DRR_D1_net (Autodesk Fusion 360 design; units mm, degrees)
part number: 2026-11-05-15-11-59-362
part number: 2026-11-05-15-12-06-884
part number: 2026-11-05-15-12-08-427
Autodesk Fusion 360 part; units mm, degrees
sketch "Sketch1" plane through (0, 0, 0) normal (0, 0, 1) x (1, 0, 0) in component "Net Posts"
  line L0 (-200, 3310) -> (200, 3310)
  line L1 (200, 3310) -> (200, 3710)
  line L2 (200, 3710) -> (-200, 3710)
  line L3 (-200, 3710) -> (-200, 3310)
  dimension "d90" = 200
  dimension "d91" = 3310
  dimension "d92" = 200
  dimension "d93" = 3710
  constraint horizontal L0.start L0.end
  constraint vertical L0.end L1.end
  constraint vertical L0.start L2.end
  constraint horizontal L1.end L2.end
  measures "d90" horizontal distance of origin L0.start
  measures "d91" vertical distance of origin L0.start
  measures "d92" horizontal distance of origin L0.end
  measures "d93" vertical distance of origin L1.end
extrude "Extrude1" add sketch "Sketch1" along normal blind 8 makes body 1 in component "Net Posts"
sketch "Sketch2" plane through (0, 0, 0) normal (0, 0, 1) x (1, 0, 0) in component "Net Posts"
  line L0 (-60, 3450) -> (60, 3450)
  line L1 (60, 3450) -> (60, 3570)
  line L2 (60, 3570) -> (-60, 3570)
  line L3 (-60, 3570) -> (-60, 3450)
  dimension "d96" = 60
  dimension "d97" = 3450
  dimension "d98" = 60
  dimension "d99" = 3570
  constraint horizontal L0.start L0.end
  constraint vertical L0.end L1.end
  constraint vertical L0.start L2.end
  constraint horizontal L1.end L2.end
  measures "d96" horizontal distance of origin L0.start
  measures "d97" vertical distance of origin L0.start
  measures "d98" horizontal distance of origin L0.end
  measures "d99" vertical distance of origin L1.end
extrude "Extrude2" add sketch "Sketch2" along normal blind 1992 from surface at 8 separate body makes body 2 in component "Net Posts"
sketch "Sketch3" plane through (0, 0, 0) normal (0, 1, 0) x (1, 0, 0) in component "Net Posts"
  line L0 (60, -1700) -> (60, -1580)
  line L1 (60, -1580) -> (1380, -8)
  line L2 (1380, -8) -> (1500, -8)
  line L3 (1500, -8) -> (60, -1700)
  dimension "d103" = 60
  dimension "d104" = 1700
  dimension "d105" = 1580
  dimension "d106" = 1380
  constraint vertical L0.start L0.end
  constraint horizontal L1.end L2.end
  measures "d103" horizontal distance of origin L0.start
  measures "d104" vertical distance of origin L0.start
  measures "d105" vertical distance of origin L0.end
  measures "d106" horizontal distance of origin L1.end
extrude "Extrude3" add sketch "Sketch3" along normal blind 80 from surface at 3470 separate body makes body 3 in component "Net Posts"
sketch "Sketch4" plane through (0, 0, 0) normal (0, 0, 1) x (1, 0, 0) in component "Net Posts"
  line L0 (1250, 3360) -> (1550, 3360)
  line L1 (1550, 3360) -> (1550, 3660)
  line L2 (1550, 3660) -> (1250, 3660)
  line L3 (1250, 3660) -> (1250, 3360)
  dimension "d112" = 1250
  dimension "d113" = 3360
  dimension "d114" = 1550
  dimension "d115" = 3660
  constraint horizontal L0.start L0.end
  constraint vertical L0.end L1.end
  constraint vertical L0.start L2.end
  constraint horizontal L1.end L2.end
  measures "d112" horizontal distance of origin L0.start
  measures "d113" vertical distance of origin L0.start
  measures "d114" horizontal distance of origin L0.end
  measures "d115" vertical distance of origin L1.end
extrude "Extrude4" add sketch "Sketch4" along normal blind 8 separate body makes body 4 in component "Net Posts"
sketch "Sketch5" plane through (0, 0, 0) normal (0, 0, 1) x (1, 0, 0) in component "Net Posts"
  line L0 (-200, -3710) -> (200, -3710)
  line L1 (200, -3710) -> (200, -3310)
  line L2 (200, -3310) -> (-200, -3310)
  line L3 (-200, -3310) -> (-200, -3710)
  dimension "d118" = 200
  dimension "d119" = 3710
  dimension "d120" = 200
  dimension "d121" = 3310
  constraint horizontal L0.start L0.end
  constraint vertical L0.end L1.end
  constraint vertical L0.start L2.end
  constraint horizontal L1.end L2.end
  measures "d118" horizontal distance of origin L0.start
  measures "d119" vertical distance of origin L0.start
  measures "d120" horizontal distance of origin L0.end
  measures "d121" vertical distance of origin L1.end
extrude "Extrude5" add sketch "Sketch5" along normal blind 8 separate body makes body 5 in component "Net Posts"
sketch "Sketch6" plane through (0, 0, 0) normal (0, 0, 1) x (1, 0, 0) in component "Net Posts"
  line L0 (-60, -3570) -> (60, -3570)
  line L1 (60, -3570) -> (60, -3450)
  line L2 (60, -3450) -> (-60, -3450)
  line L3 (-60, -3450) -> (-60, -3570)
  dimension "d124" = 60
  dimension "d125" = 3570
  dimension "d126" = 60
  dimension "d127" = 3450
  constraint horizontal L0.start L0.end
  constraint vertical L0.end L1.end
  constraint vertical L0.start L2.end
  constraint horizontal L1.end L2.end
  measures "d124" horizontal distance of origin L0.start
  measures "d125" vertical distance of origin L0.start
  measures "d126" horizontal distance of origin L0.end
  measures "d127" vertical distance of origin L1.end
extrude "Extrude6" add sketch "Sketch6" along normal blind 1992 from surface at 8 separate body makes body 6 in component "Net Posts"
sketch "Sketch7" plane through (0, 0, 0) normal (0, 1, 0) x (1, 0, 0) in component "Net Posts"
  line L0 (60, -1700) -> (60, -1580)
  line L1 (60, -1580) -> (1380, -8)
  line L2 (1380, -8) -> (1500, -8)
  line L3 (1500, -8) -> (60, -1700)
  dimension "d131" = 60
  dimension "d132" = 1700
  dimension "d133" = 1580
  dimension "d134" = 1380
  constraint vertical L0.start L0.end
  constraint horizontal L1.end L2.end
  measures "d131" horizontal distance of origin L0.start
  measures "d132" vertical distance of origin L0.start
  measures "d133" vertical distance of origin L0.end
  measures "d134" horizontal distance of origin L1.end
extrude "Extrude7" add sketch "Sketch7" along normal blind 80 from surface at -3550 separate body makes body 7 in component "Net Posts"
sketch "Sketch8" plane through (0, 0, 0) normal (0, 0, 1) x (1, 0, 0) in component "Net Posts"
  line L0 (1250, -3660) -> (1550, -3660)
  line L1 (1550, -3660) -> (1550, -3360)
  line L2 (1550, -3360) -> (1250, -3360)
  line L3 (1250, -3360) -> (1250, -3660)
  dimension "d140" = 1250
  dimension "d141" = 3660
  dimension "d142" = 1550
  dimension "d143" = 3360
  constraint horizontal L0.start L0.end
  constraint vertical L0.end L1.end
  constraint vertical L0.start L2.end
  constraint horizontal L1.end L2.end
  measures "d140" horizontal distance of origin L0.start
  measures "d141" vertical distance of origin L0.start
  measures "d142" horizontal distance of origin L0.end
  measures "d143" vertical distance of origin L1.end
extrude "Extrude8" add sketch "Sketch8" along normal blind 8 separate body makes body 8 in component "Net Posts"
sketch "Sketch1 (2)" plane through (0, 0, 0) normal (0, 0, 1) x (1, 0, 0) in component "Net Mesh"
  line L0 (-6, -3450) -> (6, -3450)
  line L1 (6, -3450) -> (6, -3438)
  line L2 (6, -3438) -> (-6, -3438)
  line L3 (-6, -3438) -> (-6, -3450)
  dimension "d146" = 6
  dimension "d147" = 3450
  dimension "d148" = 6
  dimension "d149" = 3438
  constraint horizontal L0.start L0.end
  constraint vertical L0.end L1.end
  constraint vertical L0.start L2.end
  constraint horizontal L1.end L2.end
  measures "d146" horizontal distance of origin L0.start
  measures "d147" vertical distance of origin L0.start
  measures "d148" horizontal distance of origin L0.end
  measures "d149" vertical distance of origin L1.end
extrude "Extrude1'" add sketch "Sketch1 (2)" along normal blind 1650 from surface at 150 separate body makes body 9 in component "Net Mesh"
pattern_linear "R-Pattern1" count 29 spacing 246 along (0, 1, 0) count 3 spacing 0 along (0, 1, 0) of bodies 9 makes body 10 at (-6, -3196, 1250) makes body 11 at (-6, -2950, 1250) makes body 12 at (-6, -2704, 1250) makes body 13 at (-6, -2458, 1250) makes body 14 at (-6, -2212, 1250) makes body 15 at (-6, -1966, 1250) makes body 16 at (-6, -1720, 1250) makes body 17 at (-6, -1474, 1250) makes body 18 at (-6, -1228, 1250) makes body 19 at (-6, -982, 1250) makes body 20 at (-6, -736, 1250) makes body 21 at (-6, -490, 1250) makes body 22 at (-6, -244, 1250) makes body 23 at (-6, 2, 1250) makes body 24 at (-6, 248, 1250) makes body 25 at (-6, 494, 1250) makes body 26 at (-6, 740, 1250) makes body 27 at (-6, 986, 1250) makes body 28 at (-6, 1232, 1250) makes body 29 at (-6, 1478, 1250) makes body 30 at (-6, 1724, 1250) makes body 31 at (-6, 1970, 1250) makes body 32 at (-6, 2216, 1250) makes body 33 at (-6, 2462, 1250) makes body 34 at (-6, 2708, 1250) makes body 35 at (-6, 2954, 1250) makes body 36 at (-6, 3200, 1250) makes body 37 at (-6, 3446, 1250) makes body 38 at (-6, -3442, 1250) makes body 39 at (-6, -3196, 1250) makes body 40 at (-6, -2950, 1250) makes body 41 at (-6, -2704, 1250) makes body 42 at (-6, -2458, 1250) makes body 43 at (-6, -2212, 1250) makes body 44 at (-6, -1966, 1250) makes body 45 at (-6, -1720, 1250) makes body 46 at (-6, -1474, 1250) makes body 47 at (-6, -1228, 1250) makes body 48 at (-6, -982, 1250) makes body 49 at (-6, -736, 1250) makes body 50 at (-6, -490, 1250) makes body 51 at (-6, -244, 1250) makes body 52 at (-6, 2, 1250) makes body 53 at (-6, 248, 1250) makes body 54 at (-6, 494, 1250) makes body 55 at (-6, 740, 1250) makes body 56 at (-6, 986, 1250) makes body 57 at (-6, 1232, 1250) makes body 58 at (-6, 1478, 1250) makes body 59 at (-6, 1724, 1250) makes body 60 at (-6, 1970, 1250) makes body 61 at (-6, 2216, 1250) makes body 62 at (-6, 2462, 1250) makes body 63 at (-6, 2708, 1250) makes body 64 at (-6, 2954, 1250) makes body 65 at (-6, 3200, 1250) makes body 66 at (-6, 3446, 1250) makes body 67 at (-6, -3442, 1250) makes body 68 at (-6, -3196, 1250) makes body 69 at (-6, -2950, 1250) makes body 70 at (-6, -2704, 1250) makes body 71 at (-6, -2458, 1250) makes body 72 at (-6, -2212, 1250) makes body 73 at (-6, -1966, 1250) makes body 74 at (-6, -1720, 1250) makes body 75 at (-6, -1474, 1250) makes body 76 at (-6, -1228, 1250) makes body 77 at (-6, -982, 1250) makes body 78 at (-6, -736, 1250) makes body 79 at (-6, -490, 1250) makes body 80 at (-6, -244, 1250) makes body 81 at (-6, 2, 1250) makes body 82 at (-6, 248, 1250) makes body 83 at (-6, 494, 1250) makes body 84 at (-6, 740, 1250) makes body 85 at (-6, 986, 1250) makes body 86 at (-6, 1232, 1250) makes body 87 at (-6, 1478, 1250) makes body 88 at (-6, 1724, 1250) makes body 89 at (-6, 1970, 1250) makes body 90 at (-6, 2216, 1250) makes body 91 at (-6, 2462, 1250) makes body 92 at (-6, 2708, 1250) makes body 93 at (-6, 2954, 1250) makes body 94 at (-6, 3200, 1250) makes body 95 at (-6, 3446, 1250) in component "Net Mesh"
sketch "Sketch2 (2)" plane through (0, 0, 0) normal (0, 1, 0) x (1, 0, 0) in component "Net Mesh"
  line L0 (-6, -150) -> (6, -150)
  line L1 (6, -150) -> (6, -162)
  line L2 (6, -162) -> (-6, -162)
  line L3 (-6, -162) -> (-6, -150)
  dimension "d157" = 6
  dimension "d159" = 6
  constraint horizontal L0.start L0.end
  constraint vertical L0.end L1.end
  constraint vertical L0.start L2.end
  constraint horizontal L1.end L2.end
  measures "d157" horizontal distance of origin L0.start
  measures "d159" horizontal distance of origin L0.end
extrude "Extrude2'" add sketch "Sketch2 (2)" along normal blind 6900 from surface at -3450 separate body makes body 96 in component "Net Mesh"
pattern_linear "R-Pattern2" count 8 spacing 234 along (0, 0, 1) count 3 spacing 0 along (0, 0, 1) of bodies 96 makes body 97 at (-2, 1150, 384) makes body 98 at (-2, 1150, 618) makes body 99 at (-2, 1150, 852) makes body 100 at (-2, 1150, 1086) makes body 101 at (-2, 1150, 1320) makes body 102 at (-2, 1150, 1554) makes body 103 at (-2, 1150, 1788) makes body 104 at (-2, 1150, 150) makes body 105 at (-2, 1150, 384) makes body 106 at (-2, 1150, 618) makes body 107 at (-2, 1150, 852) makes body 108 at (-2, 1150, 1086) makes body 109 at (-2, 1150, 1320) makes body 110 at (-2, 1150, 1554) makes body 111 at (-2, 1150, 1788) makes body 112 at (-2, 1150, 150) makes body 113 at (-2, 1150, 384) makes body 114 at (-2, 1150, 618) makes body 115 at (-2, 1150, 852) makes body 116 at (-2, 1150, 1086) makes body 117 at (-2, 1150, 1320) makes body 118 at (-2, 1150, 1554) makes body 119 at (-2, 1150, 1788) in component "Net Mesh"
component "Net Posts" placed x (1, 0, 0) y (0, 1, 0) z (0, 0, 1) at (0, 0, 0)
component "Net Mesh" placed x (1, 0, 0) y (0, 1, 0) z (0, 0, 1) at (0, 0, 0)
equation "drone_mass = 140.6 kg" comment "spec: drone mass (310 lb)"
equation "wingspan = 6100 mm" comment "spec: stand-in wingspan (20 ft)"
equation "body_width = 508 mm" comment "spec: body width, design value"
equation "body_drop = 254 mm" comment "spec: wing underside to body bottom"
equation "prop_dia = 700 mm" comment "spec: prop diameter, stopped blades vertical"
equation "tail_clear = 330 mm" comment "spec: tail underside above wing underside (drone requirement, 5 deg landing pitch)"
equation "landing_speed_kn = 40" comment "spec: landing speed, knots"
equation "sink_rate_ms = 1.5" comment "spec: sink rate at touchdown, m/s"
equation "grip = 0.3" comment "spec: friction coefficient, cap on wing"
equation "max_offset = 300 mm" comment "spec: side-to-side landing error"
equation "side_clear = 25 mm" comment "spec: gap between body and cap each side"
equation "rail_gap = body_width + 2 * side_clear" comment "spec: inner gap between caps"
equation "cap_width = 150 mm" comment "spec"
equation "cap_wall = 2 mm" comment "spec (was 3 mm; 2 mm for the 25 kg target)"
equation "cap_overlap = 100 mm" comment "spec: shingle overlap at joints"
equation "core_w = 50 mm" comment "spec: aluminium core tube width"
equation "core_h = 100 mm" comment "spec: aluminium core tube height"
equation "core_wall = 2 mm" comment "spec (was 3 mm; 2 mm for the 25 kg target)"
equation "rail_top_h = 700 mm" comment "spec: ground to cap top, unloaded"
equation "section_len = 2000 mm" comment "spec (was 2400 mm; 2000 mm for the 25 kg target)"
equation "frame_inset = 300 mm" comment "spec: U-frame position from section end"
equation "spring_travel = 50 mm" comment "spec"
equation "spring_rate = 90" comment "spec: N/mm per wing contact point"
equation "springs_per_cap = 2" comment "spec"
equation "section_count = 30" comment "spec: sections for the run length"
equation "model_scale = 0.1" comment "spec: printable model scale"
equation "body_len = 4000 mm" comment "spec sec 2 (assumed): stand-in body length"
equation "wing_chord = 600 mm" comment "spec sec 2 (assumed): stand-in wing chord"
equation "wing_thk = 80 mm" comment "assumed: stand-in wing thickness"
equation "tail_arm = 3000 mm" comment "assumed (spec risk 1): wing mid-chord to tail"
equation "tail_span = 1800 mm" comment "assumed: horizontal tail span"
equation "tail_chord = 400 mm" comment "assumed"
equation "tail_thk = 30 mm" comment "assumed"
equation "prop_blade_w = 60 mm" comment "assumed: blade width"
equation "prop_blade_t = 20 mm" comment "assumed"
equation "prop_disc_t = 4 mm" comment "prop disc stand-in thickness"
equation "rail_cc = rail_gap + cap_width" comment "derived: rail centre-to-centre"
equation "cap_crown = 6 mm" comment "assumed: crown rise across the cap"
equation "cap_flange_d = 35 mm" comment "assumed: cap flange depth at the edges"
equation "cap_nose_r = 25 mm" comment "assumed: rounded nose radius, upstream end"
equation "cap_tail_r = 1.5 mm" comment "assumed: edge radius, downstream (top shingle) end; below cap_wall"
equation "cap_gap = 1 mm" comment "assumed: skirt-to-core and shingle nesting gap"
equation "spring_len = 110 mm" comment "assumed: installed spring length, unloaded"
equation "spring_od = 40 mm" comment "assumed"
equation "spring_wire = 6 mm" comment "assumed"
equation "spring_coils = 8" comment "assumed: coil turns"
equation "screw_d = 8 mm" comment "assumed: M8 guide screw"
equation "screw_head_d = 16 mm" comment "assumed"
equation "screw_head_t = 5 mm" comment "assumed"
equation "screw_drop = 25 mm" comment "assumed: screw axis below core top"
equation "skirt_margin = 10 mm" comment "assumed: skirt below slot bottom"
equation "slot_clear = 1 mm" comment "assumed: slot width over screw"
equation "tongue_len = 300 mm" comment "assumed: splice tongue, half protrudes"
equation "slide_fit = 0.5 mm" comment "assumed: sliding clearance, full scale"
equation "pin_d = 10 mm" comment "assumed: ball-lock pin"
equation "pin_head_d = 25 mm" comment "assumed"
equation "pin_head_t = 8 mm" comment "assumed"
equation "pin_x1 = 50 mm" comment "assumed: pin positions past the joint"
equation "pin_x2 = 100 mm" comment "assumed"
equation "frame_tube = 40 mm" comment "assumed: U-frame square tube"
equation "frame_wall = 3 mm" comment "assumed"
equation "split_gap = 2 mm" comment "assumed: gap at the U-frame split"
equation "xbar_splice = 60 mm" comment "assumed: cross-bar splice tongue reach"
equation "frame_pin_d = 12 mm" comment "assumed: U-frame split pin"
equation "foot_h = 30 mm" comment "assumed: ground to frame underside"
equation "foot_plate_w = 150 mm" comment "assumed: bolt-down plate"
equation "foot_plate_t = 8 mm" comment "assumed"
equation "foot_bolt_d = 13 mm" comment "assumed"
equation "foot_bolt_pitch = 110 mm" comment "assumed"
equation "foot_pad_d = 80 mm" comment "assumed"
equation "foot_pad_t = 10 mm" comment "assumed"
equation "foot_stud_d = 16 mm" comment "assumed: M16 levelling stud"
equation "core_top_z = rail_top_h - cap_wall - spring_len" comment "derived"
equation "core_bot_z = core_top_z - core_h" comment "derived"
equation "screw_z = core_top_z - screw_drop" comment "derived"
equation "skirt_bot_z = screw_z - screw_d / 2 - skirt_margin" comment "derived"
equation "flange_bot_z = rail_top_h - cap_crown - cap_flange_d" comment "derived"
equation "skirt_out = core_w / 2 + cap_gap + cap_wall" comment "derived: skirt outer face from core centre"
equation "xbar_top_z = foot_h + frame_tube" comment "derived: cross-bar top (spec: 80 mm max)"
equation "net_span = wingspan + 800 mm" comment "D1 assumed: clear span between the posts (wingtips + 400 each side)"
equation "net_bot_z = 150 mm" comment "D1 assumed: net bottom edge"
equation "net_top_z = 1800 mm" comment "D1 assumed: net top edge (tail top is about 1060)"
equation "net_mesh = 250 mm" comment "D1 assumed: largest mesh opening"
equation "net_cord = 12 mm" comment "D1 assumed: net cord (square stand-in)"
equation "post_w = 120 mm" comment "D1 assumed: square steel post"
equation "post_h = net_top_z + 200 mm" comment "derived"
equation "post_plate_w = 400 mm" comment "D1 assumed: post base plate"
equation "brace_run = 1500 mm" comment "D1 assumed: back-brace foot behind the net plane"
equation "brace_w = 80 mm" comment "D1 assumed: back-brace bar"
equation "d90 = -( -post_plate_w / 2 )"
equation "d91 = ( ( net_span / 2 + post_w / 2 ) - post_plate_w / 2 )"
equation "d92 = ( post_plate_w / 2 )"
equation "d93 = ( ( net_span / 2 + post_w / 2 ) + post_plate_w / 2 )"
equation "d94 = ( foot_plate_t ) - ( 0 mm )"
equation "d96 = -( -post_w / 2 )"
equation "d97 = ( ( net_span / 2 + post_w / 2 ) - post_w / 2 )"
equation "d98 = ( post_w / 2 )"
equation "d99 = ( ( net_span / 2 + post_w / 2 ) + post_w / 2 )"
equation "d100 = foot_plate_t"
equation "d101 = ( post_h ) - ( foot_plate_t )"
equation "d103 = ( post_w / 2 )"
equation "d104 = ( net_top_z - 100 mm )"
equation "d105 = ( net_top_z - 100 mm - 1.5 * brace_w )"
equation "d106 = ( brace_run - 1.5 * brace_w )"
equation "d107 = ( foot_plate_t )"
equation "d108 = ( brace_run )"
equation "d109 = ( net_span / 2 + post_w / 2 ) - brace_w / 2"
equation "d110 = ( ( net_span / 2 + post_w / 2 ) + brace_w / 2 ) - ( ( net_span / 2 + post_w / 2 ) - brace_w / 2 )"
equation "d112 = ( brace_run - 250 mm )"
equation "d113 = ( ( net_span / 2 + post_w / 2 ) - 150 mm )"
equation "d114 = ( brace_run + 50 mm )"
equation "d115 = ( ( net_span / 2 + post_w / 2 ) + 150 mm )"
equation "d116 = ( foot_plate_t ) - ( 0 mm )"
equation "d118 = -( -post_plate_w / 2 )"
equation "d119 = -( -( net_span / 2 + post_w / 2 ) - post_plate_w / 2 )"
equation "d120 = ( post_plate_w / 2 )"
equation "d121 = -( -( net_span / 2 + post_w / 2 ) + post_plate_w / 2 )"
equation "d122 = ( foot_plate_t ) - ( 0 mm )"
equation "d124 = -( -post_w / 2 )"
equation "d125 = -( -( net_span / 2 + post_w / 2 ) - post_w / 2 )"
equation "d126 = ( post_w / 2 )"
equation "d127 = -( -( net_span / 2 + post_w / 2 ) + post_w / 2 )"
equation "d128 = foot_plate_t"
equation "d129 = ( post_h ) - ( foot_plate_t )"
equation "d131 = ( post_w / 2 )"
equation "d132 = ( net_top_z - 100 mm )"
equation "d133 = ( net_top_z - 100 mm - 1.5 * brace_w )"
equation "d134 = ( brace_run - 1.5 * brace_w )"
equation "d135 = ( foot_plate_t )"
equation "d136 = ( brace_run )"
equation "d137 = -( net_span / 2 + post_w / 2 ) - brace_w / 2"
equation "d138 = ( -( net_span / 2 + post_w / 2 ) + brace_w / 2 ) - ( -( net_span / 2 + post_w / 2 ) - brace_w / 2 )"
equation "d140 = ( brace_run - 250 mm )"
equation "d141 = -( -( net_span / 2 + post_w / 2 ) - 150 mm )"
equation "d142 = ( brace_run + 50 mm )"
equation "d143 = -( -( net_span / 2 + post_w / 2 ) + 150 mm )"
equation "d144 = ( foot_plate_t ) - ( 0 mm )"
equation "d146 = -( -net_cord / 2 )"
equation "d147 = -( -net_span / 2 )"
equation "d148 = ( net_cord / 2 )"
equation "d149 = -( -net_span / 2 + net_cord )"
equation "d150 = net_bot_z"
equation "d151 = ( net_top_z ) - ( net_bot_z )"
equation "d155 = ( net_span - net_cord ) / 28"
equation "d157 = -( -net_cord / 2 )"
equation "d158 = ( net_bot_z )"
equation "d159 = ( net_cord / 2 )"
equation "d160 = ( net_bot_z + net_cord )"
equation "d161 = -net_span / 2"
equation "d162 = ( net_span / 2 ) - ( -net_span / 2 )"
equation "d166 = ( net_top_z - net_bot_z - net_cord ) / 7"
named bodies: "Post Plate R", "Post R", "Brace R", "Brace Plate R", "Post Plate L", "Post L", "Brace L", "Brace Plate L", "Net Cord V", "Net Cord V (1)", "Net Cord V (2)", "Net Cord V (3)", "Net Cord V (4)", "Net Cord V (5)", "Net Cord V (6)", "Net Cord V (7)", "Net Cord V (8)", "Net Cord V (9)", "Net Cord V (10)", "Net Cord V (11)", "Net Cord V (12)", "Net Cord V (13)", "Net Cord V (14)", "Net Cord V (15)", "Net Cord V (16)", "Net Cord V (17)", "Net Cord V (18)", "Net Cord V (19)", "Net Cord V (20)", "Net Cord V (21)", "Net Cord V (22)", "Net Cord V (23)", "Net Cord V (24)", "Net Cord V (25)", "Net Cord V (26)", "Net Cord V (27)", "Net Cord V (28)", "Net Cord V (29)", "Net Cord V (30)", "Net Cord V (31)", "Net Cord V (32)", "Net Cord V (33)", "Net Cord V (34)", "Net Cord V (35)", "Net Cord V (36)", "Net Cord V (37)", "Net Cord V (38)", "Net Cord V (39)", "Net Cord V (40)", "Net Cord V (41)", "Net Cord V (42)", "Net Cord V (43)", "Net Cord V (44)", "Net Cord V (45)", "Net Cord V (46)", "Net Cord V (47)", "Net Cord V (48)", "Net Cord V (49)", "Net Cord V (50)", "Net Cord V (51)", "Net Cord V (52)", "Net Cord V (53)", "Net Cord V (54)", "Net Cord V (55)", "Net Cord V (56)", "Net Cord V (57)", "Net Cord V (58)", "Net Cord V (59)", "Net Cord V (60)", "Net Cord V (61)", "Net Cord V (62)", "Net Cord V (63)", "Net Cord V (64)", "Net Cord V (65)", "Net Cord V (66)", "Net Cord V (67)", "Net Cord V (68)", "Net Cord V (69)", "Net Cord V (70)", "Net Cord V (71)", "Net Cord V (72)", "Net Cord V (73)", "Net Cord V (74)", "Net Cord V (75)", "Net Cord V (76)", "Net Cord V (77)", "Net Cord V (78)", "Net Cord V (79)", "Net Cord V (80)", "Net Cord V (81)", "Net Cord V (82)", "Net Cord V (83)", "Net Cord V (84)", "Net Cord V (85)", "Net Cord V (86)", "Net Cord H", "Net Cord H (1)", "Net Cord H (2)", "Net Cord H (3)", "Net Cord H (4)", "Net Cord H (5)", "Net Cord H (6)", "Net Cord H (7)", "Net Cord H (8)", "Net Cord H (9)", "Net Cord H (10)", "Net Cord H (11)", "Net Cord H (12)", "Net Cord H (13)", "Net Cord H (14)", "Net Cord H (15)", "Net Cord H (16)", "Net Cord H (17)", "Net Cord H (18)", "Net Cord H (19)", "Net Cord H (20)", "Net Cord H (21)", "Net Cord H (22)", "Net Cord H (23)"
